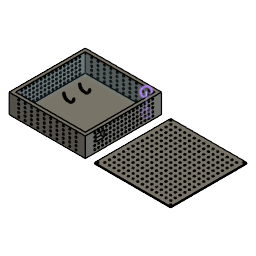
Air Quailty (Autodesk Fusion 360 design; units mm, degrees)
part number: 2026-01-30-16-34-56-412
Autodesk Fusion 360 part; units mm, degrees
sketch "Sketch1" plane through (0, 0, 0) normal (0, 1, 0) x (1, 0, 0)
  line L0 (52.5, -52.5) -> (-52.5, -52.5)
  line L1 (-52.5, -52.5) -> (-52.5, 52.5)
  line L2 (-52.5, 52.5) -> (52.5, 52.5)
  line L3 (52.5, 52.5) -> (52.5, -52.5)
  line L4 (52.5, -52.5) -> (-52.5, 52.5) construction
  line L5 (-52.5, -52.5) -> (52.5, 52.5) construction
  dimension "d1" = 105
  dimension "d2" = 105
  constraint horizontal L0
  constraint perpendicular L0 L1
  constraint parallel L0 L2
  constraint parallel L1 L3
  constraint coincident L4 origin
  constraint coincident L5 origin
  measures "d1" distance of L1.end L2.end
  measures "d2" distance of L0.end L1.end
extrude "Extrude1" add sketch "Sketch1" along normal blind 2 makes body 1
sketch "Sketch2" plane through (0, 2, 0) normal (0, 1, 0) x (-1, 0, 0)
  line L0 (-52.5, -52.5) -> (52.5, -52.5)
  line L1 (52.5, -52.5) -> (52.5, 52.5)
  line L2 (52.5, 52.5) -> (-52.5, 52.5)
  line L3 (-52.5, 52.5) -> (-52.5, -52.5)
  line L4 (-51.5, 51.5) -> (51.5, -51.5) construction
  line L5 (51.5, 51.5) -> (-51.5, -51.5) construction
  line L6 (-52.5, 52.5) -> (52.5, 52.5)
  line L7 (52.5, 52.5) -> (52.5, -52.5)
  line L8 (52.5, -52.5) -> (-52.5, -52.5)
  line L9 (-52.5, -52.5) -> (-52.5, 52.5)
  line L10 (-52.5, 52.5) -> (52.5, -52.5) construction
  line L11 (52.5, 52.5) -> (-52.5, -52.5) construction
  line L12 (50, 50) -> (-50, 50)
  line L13 (-50, 50) -> (-50, -50)
  line L14 (-50, -50) -> (50, -50)
  line L15 (50, -50) -> (50, 50)
  line L16 (50, 50) -> (-50, -50) construction
  line L17 (-50, 50) -> (50, -50) construction
  dimension "d5" = 103
  dimension "d6" = 103
  dimension "d7" = 105
  dimension "d8" = 105
  dimension "d9" = 100
  dimension "d10" = 100
  constraint coincident L4 origin
  constraint coincident L5 origin
  constraint horizontal L6
  constraint perpendicular L6 L7
  constraint parallel L6 L8
  constraint parallel L7 L9
  constraint coincident L10 origin
  constraint coincident L11 origin
  constraint horizontal L12
  constraint perpendicular L12 L13
  constraint parallel L12 L14
  constraint parallel L13 L15
  constraint coincident L16 origin
  constraint coincident L17 origin
  measures "d5" distance of L4.end L5.end
  measures "d6" distance of L5.start L4.end
  measures "d7" distance of L0.end L0.start
  measures "d8" distance of L1.end L0.end
  measures "d9" distance of L13.end L14.end
  measures "d10" distance of L12.end L13.end
extrude "Extrude2" add sketch "Sketch2" along normal blind 30 bodies 1
sketch "Sketch3" plane through (0, 0, -52.5) normal (0, 0, -1) x (-1, 0, 0)
  line L0 (-52.5, 0) -> (52.5, 0)
  line L1 (52.5, 0) -> (52.5, 32)
  line L2 (52.5, 32) -> (-52.5, 32)
  line L3 (-52.5, 32) -> (-52.5, 0)
  line L4 (-50, 2, -2.5) -> (-50, 32, -2.5)
sketch "Sketch4" plane through (0, 0, -50) normal (0, 0, 1) x (1, 0, 0)
  line L0 (-50, 2) -> (50, 2)
  line L1 (50, 2) -> (50, 32)
  line L2 (50, 32) -> (-50, 32)
  line L3 (-50, 32) -> (-50, 2)
  circle A0 centre (47.3769, 4.8478) radius 1.5
  circle A1 centre (36.9324, 4.8478) radius 1.5
  circle A2 centre (26.488, 4.8478) radius 1.5
  circle A3 centre (16.0435, 4.8478) radius 1.5
  circle A4 centre (5.5991, 4.8478) radius 1.5
  circle A5 centre (-4.8453, 4.8478) radius 1.5
  circle A6 centre (-15.2898, 4.8478) radius 1.5
  circle A7 centre (-25.7342, 4.8478) radius 1.5
  circle A8 centre (-36.1787, 4.8478) radius 1.5
  circle A9 centre (-46.6231, 4.8478) radius 1.5
  circle A10 centre (47.3769, 10.8478) radius 1.5
  circle A11 centre (36.9324, 10.8478) radius 1.5
  circle A12 centre (26.488, 10.8478) radius 1.5
  circle A13 centre (16.0435, 10.8478) radius 1.5
  circle A14 centre (5.5991, 10.8478) radius 1.5
  circle A15 centre (-4.8453, 10.8478) radius 1.5
  circle A16 centre (-15.2898, 10.8478) radius 1.5
  circle A17 centre (-25.7342, 10.8478) radius 1.5
  circle A18 centre (-36.1787, 10.8478) radius 1.5
  circle A19 centre (-46.6231, 10.8478) radius 1.5
  circle A20 centre (47.3769, 16.8478) radius 1.5
  circle A21 centre (36.9324, 16.8478) radius 1.5
  circle A22 centre (26.488, 16.8478) radius 1.5
  circle A23 centre (16.0435, 16.8478) radius 1.5
  circle A24 centre (5.5991, 16.8478) radius 1.5
  circle A25 centre (-4.8453, 16.8478) radius 1.5
  circle A26 centre (-15.2898, 16.8478) radius 1.5
  circle A27 centre (-25.7342, 16.8478) radius 1.5
  circle A28 centre (-36.1787, 16.8478) radius 1.5
  circle A29 centre (-46.6231, 16.8478) radius 1.5
  circle A30 centre (47.3769, 22.8478) radius 1.5
  circle A31 centre (36.9324, 22.8478) radius 1.5
  circle A32 centre (26.488, 22.8478) radius 1.5
  circle A33 centre (16.0435, 22.8478) radius 1.5
  circle A34 centre (5.5991, 22.8478) radius 1.5
  circle A35 centre (-4.8453, 22.8478) radius 1.5
  circle A36 centre (-15.2898, 22.8478) radius 1.5
  circle A37 centre (-25.7342, 22.8478) radius 1.5
  circle A38 centre (-36.1787, 22.8478) radius 1.5
  circle A39 centre (-46.6231, 22.8478) radius 1.5
  circle A40 centre (47.3769, 28.8478) radius 1.5
  circle A41 centre (36.9324, 28.8478) radius 1.5
  circle A42 centre (26.488, 28.8478) radius 1.5
  circle A43 centre (16.0435, 28.8478) radius 1.5
  circle A44 centre (5.5991, 28.8478) radius 1.5
  circle A45 centre (-4.8453, 28.8478) radius 1.5
  circle A46 centre (-15.2898, 28.8478) radius 1.5
  circle A47 centre (-25.7342, 28.8478) radius 1.5
  circle A48 centre (-36.1787, 28.8478) radius 1.5
  circle A49 centre (-46.6231, 28.8478) radius 1.5
  dimension "d14" = 3
  dimension "d17" = 94
  dimension "d18" = -24
  measures "d14" diameter of A0
extrude "Extrude3" cut sketch "Sketch4" along normal blind 124 and the other way blind 26 contours A0 | A1 | A2 | A3 | A4 | A5 | A6 | A7 | A8 | A9 | A10 | A11 | A12 | A13 | A14 | A15 | A16 | A17 | A18 | A19 | A20 | A21 | A22 | A23 | A24 | A25 | A26 | A27 | A28 | A29 | A30 | A31 | A32 | A33 | A34 | A35 | A36 | A37 | A38 | A39 | A40 | A41 | A42 | A43 | A44 | A45 | A46 | A47 | A48 | A49 bodies 1
sketch "Sketch5" plane through (-52.5, 0, 0) normal (-1, 0, 0) x (0, 0, 1)
  line L0 (-52.5, 0) -> (52.5, 0)
  line L1 (52.5, 0) -> (52.5, 32)
  line L2 (52.5, 32) -> (-52.5, 32)
  line L3 (-52.5, 32) -> (-52.5, 0)
sketch "Sketch6" plane through (-50, 0, 0) normal (1, 0, 0) x (0, 0, -1)
  line L0 (-50, 2) -> (50, 2)
  line L1 (50, 2) -> (50, 32)
  line L2 (50, 32) -> (-50, 32)
  line L3 (-50, 32) -> (-50, 2)
  circle A0 centre (-47, 5) radius 1.5
  circle A1 centre (-40.6667, 5) radius 1.5
  line L4 (56.3333, 32) -> (-43.6667, 32)
  line L5 (-43.6667, 32) -> (-43.6667, 2)
  circle A2 centre (-34.3333, 5) radius 1.5
  line L6 (62.6667, 32) -> (-37.3333, 32)
  line L7 (-37.3333, 32) -> (-37.3333, 2)
  circle A3 centre (-28, 5) radius 1.5
  line L8 (69, 32) -> (-31, 32)
  line L9 (-31, 32) -> (-31, 2)
  circle A4 centre (-21.6667, 5) radius 1.5
  line L10 (75.3333, 32) -> (-24.6667, 32)
  line L11 (-24.6667, 32) -> (-24.6667, 2)
  circle A5 centre (-15.3333, 5) radius 1.5
  line L12 (81.6667, 32) -> (-18.3333, 32)
  line L13 (-18.3333, 32) -> (-18.3333, 2)
  circle A6 centre (-9, 5) radius 1.5
  line L14 (88, 32) -> (-12, 32)
  line L15 (-12, 32) -> (-12, 2)
  circle A7 centre (-2.6667, 5) radius 1.5
  line L16 (94.3333, 32) -> (-5.6667, 32)
  line L17 (-5.6667, 32) -> (-5.6667, 2)
  circle A8 centre (3.6667, 5) radius 1.5
  line L18 (100.6667, 32) -> (0.6667, 32)
  line L19 (0.6667, 32) -> (0.6667, 2)
  circle A9 centre (10, 5) radius 1.5
  line L20 (107, 32) -> (7, 32)
  line L21 (7, 32) -> (7, 2)
  circle A10 centre (16.3333, 5) radius 1.5
  line L22 (113.3333, 32) -> (13.3333, 32)
  line L23 (13.3333, 32) -> (13.3333, 2)
  circle A11 centre (22.6667, 5) radius 1.5
  line L24 (119.6667, 32) -> (19.6667, 32)
  line L25 (19.6667, 32) -> (19.6667, 2)
  circle A12 centre (29, 5) radius 1.5
  line L26 (126, 32) -> (26, 32)
  line L27 (26, 32) -> (26, 2)
  circle A13 centre (35.3333, 5) radius 1.5
  line L28 (132.3333, 32) -> (32.3333, 32)
  line L29 (32.3333, 32) -> (32.3333, 2)
  circle A14 centre (41.6667, 5) radius 1.5
  line L30 (138.6667, 32) -> (38.6667, 32)
  line L31 (38.6667, 32) -> (38.6667, 2)
  circle A15 centre (48, 5) radius 1.5
  line L32 (145, 32) -> (45, 32)
  line L33 (45, 32) -> (45, 2)
  circle A16 centre (-47, 11) radius 1.5
  line L34 (50, 38) -> (-50, 38)
  line L35 (-50, 38) -> (-50, 8)
  circle A17 centre (-40.6667, 11) radius 1.5
  line L36 (56.3333, 38) -> (-43.6667, 38)
  line L37 (-43.6667, 38) -> (-43.6667, 8)
  circle A18 centre (-34.3333, 11) radius 1.5
  line L38 (62.6667, 38) -> (-37.3333, 38)
  line L39 (-37.3333, 38) -> (-37.3333, 8)
  circle A19 centre (-28, 11) radius 1.5
  line L40 (69, 38) -> (-31, 38)
  line L41 (-31, 38) -> (-31, 8)
  circle A20 centre (-21.6667, 11) radius 1.5
  line L42 (75.3333, 38) -> (-24.6667, 38)
  line L43 (-24.6667, 38) -> (-24.6667, 8)
  circle A21 centre (-15.3333, 11) radius 1.5
  line L44 (81.6667, 38) -> (-18.3333, 38)
  line L45 (-18.3333, 38) -> (-18.3333, 8)
  circle A22 centre (-9, 11) radius 1.5
  line L46 (88, 38) -> (-12, 38)
  line L47 (-12, 38) -> (-12, 8)
  circle A23 centre (-2.6667, 11) radius 1.5
  line L48 (94.3333, 38) -> (-5.6667, 38)
  line L49 (-5.6667, 38) -> (-5.6667, 8)
  circle A24 centre (3.6667, 11) radius 1.5
  line L50 (100.6667, 38) -> (0.6667, 38)
  line L51 (0.6667, 38) -> (0.6667, 8)
  circle A25 centre (10, 11) radius 1.5
  line L52 (107, 38) -> (7, 38)
  line L53 (7, 38) -> (7, 8)
  circle A26 centre (16.3333, 11) radius 1.5
  line L54 (113.3333, 38) -> (13.3333, 38)
  line L55 (13.3333, 38) -> (13.3333, 8)
  circle A27 centre (22.6667, 11) radius 1.5
  line L56 (119.6667, 38) -> (19.6667, 38)
  line L57 (19.6667, 38) -> (19.6667, 8)
  circle A28 centre (29, 11) radius 1.5
  line L58 (126, 38) -> (26, 38)
  line L59 (26, 38) -> (26, 8)
  circle A29 centre (35.3333, 11) radius 1.5
  line L60 (132.3333, 38) -> (32.3333, 38)
  line L61 (32.3333, 38) -> (32.3333, 8)
  circle A30 centre (41.6667, 11) radius 1.5
  line L62 (138.6667, 38) -> (38.6667, 38)
  line L63 (38.6667, 38) -> (38.6667, 8)
  circle A31 centre (48, 11) radius 1.5
  line L64 (145, 38) -> (45, 38)
  line L65 (45, 38) -> (45, 8)
  circle A32 centre (-47, 17) radius 1.5
  line L66 (50, 44) -> (-50, 44)
  line L67 (-50, 44) -> (-50, 14)
  circle A33 centre (-40.6667, 17) radius 1.5
  line L68 (56.3333, 44) -> (-43.6667, 44)
  line L69 (-43.6667, 44) -> (-43.6667, 14)
  circle A34 centre (-34.3333, 17) radius 1.5
  line L70 (62.6667, 44) -> (-37.3333, 44)
  line L71 (-37.3333, 44) -> (-37.3333, 14)
  circle A35 centre (-28, 17) radius 1.5
  line L72 (69, 44) -> (-31, 44)
  line L73 (-31, 44) -> (-31, 14)
  circle A36 centre (-21.6667, 17) radius 1.5
  line L74 (75.3333, 44) -> (-24.6667, 44)
  line L75 (-24.6667, 44) -> (-24.6667, 14)
  circle A37 centre (-15.3333, 17) radius 1.5
  line L76 (81.6667, 44) -> (-18.3333, 44)
  line L77 (-18.3333, 44) -> (-18.3333, 14)
  circle A38 centre (-9, 17) radius 1.5
  line L78 (88, 44) -> (-12, 44)
  line L79 (-12, 44) -> (-12, 14)
  circle A39 centre (-2.6667, 17) radius 1.5
  line L80 (94.3333, 44) -> (-5.6667, 44)
  line L81 (-5.6667, 44) -> (-5.6667, 14)
  circle A40 centre (3.6667, 17) radius 1.5
  line L82 (100.6667, 44) -> (0.6667, 44)
  line L83 (0.6667, 44) -> (0.6667, 14)
  circle A41 centre (10, 17) radius 1.5
  line L84 (107, 44) -> (7, 44)
  line L85 (7, 44) -> (7, 14)
  circle A42 centre (16.3333, 17) radius 1.5
  line L86 (113.3333, 44) -> (13.3333, 44)
  line L87 (13.3333, 44) -> (13.3333, 14)
  circle A43 centre (22.6667, 17) radius 1.5
  line L88 (119.6667, 44) -> (19.6667, 44)
  line L89 (19.6667, 44) -> (19.6667, 14)
  circle A44 centre (29, 17) radius 1.5
  line L90 (126, 44) -> (26, 44)
  line L91 (26, 44) -> (26, 14)
  circle A45 centre (35.3333, 17) radius 1.5
  line L92 (132.3333, 44) -> (32.3333, 44)
  line L93 (32.3333, 44) -> (32.3333, 14)
  circle A46 centre (41.6667, 17) radius 1.5
  line L94 (138.6667, 44) -> (38.6667, 44)
  line L95 (38.6667, 44) -> (38.6667, 14)
  circle A47 centre (48, 17) radius 1.5
  line L96 (145, 44) -> (45, 44)
  line L97 (45, 44) -> (45, 14)
  circle A48 centre (-47, 23) radius 1.5
  line L98 (50, 50) -> (-50, 50)
  line L99 (-50, 50) -> (-50, 20)
  circle A49 centre (-40.6667, 23) radius 1.5
  line L100 (56.3333, 50) -> (-43.6667, 50)
  line L101 (-43.6667, 50) -> (-43.6667, 20)
  circle A50 centre (-34.3333, 23) radius 1.5
  line L102 (62.6667, 50) -> (-37.3333, 50)
  line L103 (-37.3333, 50) -> (-37.3333, 20)
  circle A51 centre (-28, 23) radius 1.5
  line L104 (69, 50) -> (-31, 50)
  line L105 (-31, 50) -> (-31, 20)
  circle A52 centre (-21.6667, 23) radius 1.5
  line L106 (75.3333, 50) -> (-24.6667, 50)
  line L107 (-24.6667, 50) -> (-24.6667, 20)
  circle A53 centre (-15.3333, 23) radius 1.5
  line L108 (81.6667, 50) -> (-18.3333, 50)
  line L109 (-18.3333, 50) -> (-18.3333, 20)
  circle A54 centre (-9, 23) radius 1.5
  line L110 (88, 50) -> (-12, 50)
  line L111 (-12, 50) -> (-12, 20)
  circle A55 centre (-2.6667, 23) radius 1.5
  line L112 (94.3333, 50) -> (-5.6667, 50)
  line L113 (-5.6667, 50) -> (-5.6667, 20)
  circle A56 centre (3.6667, 23) radius 1.5
  line L114 (100.6667, 50) -> (0.6667, 50)
  line L115 (0.6667, 50) -> (0.6667, 20)
  circle A57 centre (10, 23) radius 1.5
  line L116 (107, 50) -> (7, 50)
  line L117 (7, 50) -> (7, 20)
  circle A58 centre (16.3333, 23) radius 1.5
  line L118 (113.3333, 50) -> (13.3333, 50)
  line L119 (13.3333, 50) -> (13.3333, 20)
  circle A59 centre (22.6667, 23) radius 1.5
  line L120 (119.6667, 50) -> (19.6667, 50)
  line L121 (19.6667, 50) -> (19.6667, 20)
  circle A60 centre (29, 23) radius 1.5
  line L122 (126, 50) -> (26, 50)
  line L123 (26, 50) -> (26, 20)
  circle A61 centre (35.3333, 23) radius 1.5
  line L124 (132.3333, 50) -> (32.3333, 50)
  line L125 (32.3333, 50) -> (32.3333, 20)
  circle A62 centre (41.6667, 23) radius 1.5
  line L126 (138.6667, 50) -> (38.6667, 50)
  line L127 (38.6667, 50) -> (38.6667, 20)
  circle A63 centre (48, 23) radius 1.5
  line L128 (145, 50) -> (45, 50)
  line L129 (45, 50) -> (45, 20)
  circle A64 centre (-47, 29) radius 1.5
  line L130 (50, 56) -> (-50, 56)
  line L131 (-50, 56) -> (-50, 26)
  circle A65 centre (-40.6667, 29) radius 1.5
  line L132 (56.3333, 56) -> (-43.6667, 56)
  line L133 (-43.6667, 56) -> (-43.6667, 26)
  circle A66 centre (-34.3333, 29) radius 1.5
  line L134 (62.6667, 56) -> (-37.3333, 56)
  line L135 (-37.3333, 56) -> (-37.3333, 26)
  circle A67 centre (-28, 29) radius 1.5
  line L136 (69, 56) -> (-31, 56)
  line L137 (-31, 56) -> (-31, 26)
  circle A68 centre (-21.6667, 29) radius 1.5
  line L138 (75.3333, 56) -> (-24.6667, 56)
  line L139 (-24.6667, 56) -> (-24.6667, 26)
  circle A69 centre (-15.3333, 29) radius 1.5
  line L140 (81.6667, 56) -> (-18.3333, 56)
  line L141 (-18.3333, 56) -> (-18.3333, 26)
  circle A70 centre (-9, 29) radius 1.5
  line L142 (88, 56) -> (-12, 56)
  line L143 (-12, 56) -> (-12, 26)
  circle A71 centre (-2.6667, 29) radius 1.5
  line L144 (94.3333, 56) -> (-5.6667, 56)
  line L145 (-5.6667, 56) -> (-5.6667, 26)
  circle A72 centre (3.6667, 29) radius 1.5
  line L146 (100.6667, 56) -> (0.6667, 56)
  line L147 (0.6667, 56) -> (0.6667, 26)
  circle A73 centre (10, 29) radius 1.5
  line L148 (107, 56) -> (7, 56)
  line L149 (7, 56) -> (7, 26)
  circle A74 centre (16.3333, 29) radius 1.5
  line L150 (113.3333, 56) -> (13.3333, 56)
  line L151 (13.3333, 56) -> (13.3333, 26)
  circle A75 centre (22.6667, 29) radius 1.5
  line L152 (119.6667, 56) -> (19.6667, 56)
  line L153 (19.6667, 56) -> (19.6667, 26)
  circle A76 centre (29, 29) radius 1.5
  line L154 (126, 56) -> (26, 56)
  line L155 (26, 56) -> (26, 26)
  circle A77 centre (35.3333, 29) radius 1.5
  line L156 (132.3333, 56) -> (32.3333, 56)
  line L157 (32.3333, 56) -> (32.3333, 26)
  circle A78 centre (41.6667, 29) radius 1.5
  line L158 (138.6667, 56) -> (38.6667, 56)
  line L159 (38.6667, 56) -> (38.6667, 26)
  circle A79 centre (48, 29) radius 1.5
  line L160 (145, 56) -> (45, 56)
  line L161 (45, 56) -> (45, 26)
  dimension "d23" = 3
  dimension "d26" = 95
  dimension "d27" = 24
  measures "d23" diameter of A0
extrude "Extrude4" cut sketch "Sketch6" along normal blind 119 and the other way blind 26 contours A0 | A1 | A2 | A3 | A16 | A17 | A18 | A19 | A32 | A33 | A34 | A35 | A48 | A49 | A50 | A51 | A64 | A65 | A66 | A67 bodies 1
extrude "Extrude5" cut sketch "Sketch6" along normal mid plane 250 contours A4 | A5 | A6 | A7 | A8 | A9 | A20 | A21 | A22 | A23 | A24 | A25 | A36 | A37 | A38 | A39 | A40 | A41 | A52 | A53 | A54 | A55 | A56 | A57 | A68 | A69 | A70 | A71 | A72 | A73 bodies 1
extrude "Extrude6" cut sketch "Sketch6" along normal blind 125 and the other way blind 9 contours A10 | A11 | A12 | A13 | A14 | A15 | A26 | A27 | A28 | A29 | A30 | A31 | A42 | A43 | A44 | A45 | A46 | A47 | A58 | A59 | A60 | A61 | A62 | A63 | A74 | A75 | A76 | A77 | A78 | A79 bodies 1
move_face "OffsetFaces1" offset -2 4 faces at (-50, 20.6599, -20.189) (-8.7773, 20.6309, -50) (50, 19.3401, 6.5224) (-11.3578, 19.0647, 50) on bodies 1
sketch "Sketch8" plane through (0, 32, 0) normal (0, 1, 0) x (-1, 0, 0)
  line L0 (-52.5, -52.5) -> (52.5, -52.5)
  line L1 (52.5, -52.5) -> (52.5, 52.5)
  line L2 (52.5, 52.5) -> (-52.5, 52.5)
  line L3 (-52.5, 52.5) -> (-52.5, -52.5)
  circle A0 centre (-50.25, 50.25) radius 1.5
  circle A1 centre (50.25, 50.25) radius 1.5
  circle A2 centre (-50.25, -50.25) radius 1.5
  circle A3 centre (50.25, -50.25) radius 1.5
  circle A4 centre (-45, 45) radius 1.5
  circle A5 centre (-38.6429, 45) radius 1.5
  circle A6 centre (-32.2857, 45) radius 1.5
  circle A7 centre (-25.9286, 45) radius 1.5
  circle A8 centre (-19.5714, 45) radius 1.5
  circle A9 centre (-13.2143, 45) radius 1.5
  circle A10 centre (-6.8571, 45) radius 1.5
  circle A11 centre (-0.5, 45) radius 1.5
  circle A12 centre (5.8571, 45) radius 1.5
  circle A13 centre (12.2143, 45) radius 1.5
  circle A14 centre (18.5714, 45) radius 1.5
  circle A15 centre (24.9286, 45) radius 1.5
  circle A16 centre (31.2857, 45) radius 1.5
  circle A17 centre (37.6429, 45) radius 1.5
  circle A18 centre (44, 45) radius 1.5
  circle A19 centre (-45, 38.6429) radius 1.5
  circle A20 centre (-38.6429, 38.6429) radius 1.5
  circle A21 centre (-32.2857, 38.6429) radius 1.5
  circle A22 centre (-25.9286, 38.6429) radius 1.5
  circle A23 centre (-19.5714, 38.6429) radius 1.5
  circle A24 centre (-13.2143, 38.6429) radius 1.5
  circle A25 centre (-6.8571, 38.6429) radius 1.5
  circle A26 centre (-0.5, 38.6429) radius 1.5
  circle A27 centre (5.8571, 38.6429) radius 1.5
  circle A28 centre (12.2143, 38.6429) radius 1.5
  circle A29 centre (18.5714, 38.6429) radius 1.5
  circle A30 centre (24.9286, 38.6429) radius 1.5
  circle A31 centre (31.2857, 38.6429) radius 1.5
  circle A32 centre (37.6429, 38.6429) radius 1.5
  circle A33 centre (44, 38.6429) radius 1.5
  circle A34 centre (-45, 32.2857) radius 1.5
  circle A35 centre (-38.6429, 32.2857) radius 1.5
  circle A36 centre (-32.2857, 32.2857) radius 1.5
  circle A37 centre (-25.9286, 32.2857) radius 1.5
  circle A38 centre (-19.5714, 32.2857) radius 1.5
  circle A39 centre (-13.2143, 32.2857) radius 1.5
  circle A40 centre (-6.8571, 32.2857) radius 1.5
  circle A41 centre (-0.5, 32.2857) radius 1.5
  circle A42 centre (5.8571, 32.2857) radius 1.5
  circle A43 centre (12.2143, 32.2857) radius 1.5
  circle A44 centre (18.5714, 32.2857) radius 1.5
  circle A45 centre (24.9286, 32.2857) radius 1.5
  circle A46 centre (31.2857, 32.2857) radius 1.5
  circle A47 centre (37.6429, 32.2857) radius 1.5
  circle A48 centre (44, 32.2857) radius 1.5
  circle A49 centre (-45, 25.9286) radius 1.5
  circle A50 centre (-38.6429, 25.9286) radius 1.5
  circle A51 centre (-32.2857, 25.9286) radius 1.5
  circle A52 centre (-25.9286, 25.9286) radius 1.5
  circle A53 centre (-19.5714, 25.9286) radius 1.5
  circle A54 centre (-13.2143, 25.9286) radius 1.5
  circle A55 centre (-6.8571, 25.9286) radius 1.5
  circle A56 centre (-0.5, 25.9286) radius 1.5
  circle A57 centre (5.8571, 25.9286) radius 1.5
  circle A58 centre (12.2143, 25.9286) radius 1.5
  circle A59 centre (18.5714, 25.9286) radius 1.5
  circle A60 centre (24.9286, 25.9286) radius 1.5
  circle A61 centre (31.2857, 25.9286) radius 1.5
  circle A62 centre (37.6429, 25.9286) radius 1.5
  circle A63 centre (44, 25.9286) radius 1.5
  circle A64 centre (-45, 19.5714) radius 1.5
  circle A65 centre (-38.6429, 19.5714) radius 1.5
  circle A66 centre (-32.2857, 19.5714) radius 1.5
  circle A67 centre (-25.9286, 19.5714) radius 1.5
  circle A68 centre (-19.5714, 19.5714) radius 1.5
  circle A69 centre (-13.2143, 19.5714) radius 1.5
  circle A70 centre (-6.8571, 19.5714) radius 1.5
  circle A71 centre (-0.5, 19.5714) radius 1.5
  circle A72 centre (5.8571, 19.5714) radius 1.5
  circle A73 centre (12.2143, 19.5714) radius 1.5
  circle A74 centre (18.5714, 19.5714) radius 1.5
  circle A75 centre (24.9286, 19.5714) radius 1.5
  circle A76 centre (31.2857, 19.5714) radius 1.5
  circle A77 centre (37.6429, 19.5714) radius 1.5
  circle A78 centre (44, 19.5714) radius 1.5
  circle A79 centre (-45, 13.2143) radius 1.5
  circle A80 centre (-38.6429, 13.2143) radius 1.5
  circle A81 centre (-32.2857, 13.2143) radius 1.5
  circle A82 centre (-25.9286, 13.2143) radius 1.5
  circle A83 centre (-19.5714, 13.2143) radius 1.5
  circle A84 centre (-13.2143, 13.2143) radius 1.5
  circle A85 centre (-6.8571, 13.2143) radius 1.5
  circle A86 centre (-0.5, 13.2143) radius 1.5
  circle A87 centre (5.8571, 13.2143) radius 1.5
  circle A88 centre (12.2143, 13.2143) radius 1.5
  circle A89 centre (18.5714, 13.2143) radius 1.5
  circle A90 centre (24.9286, 13.2143) radius 1.5
  circle A91 centre (31.2857, 13.2143) radius 1.5
  circle A92 centre (37.6429, 13.2143) radius 1.5
  circle A93 centre (44, 13.2143) radius 1.5
  circle A94 centre (-45, 6.8571) radius 1.5
  circle A95 centre (-38.6429, 6.8571) radius 1.5
  circle A96 centre (-32.2857, 6.8571) radius 1.5
  circle A97 centre (-25.9286, 6.8571) radius 1.5
  circle A98 centre (-19.5714, 6.8571) radius 1.5
  circle A99 centre (-13.2143, 6.8571) radius 1.5
  circle A100 centre (-6.8571, 6.8571) radius 1.5
  circle A101 centre (-0.5, 6.8571) radius 1.5
  circle A102 centre (5.8571, 6.8571) radius 1.5
  circle A103 centre (12.2143, 6.8571) radius 1.5
  circle A104 centre (18.5714, 6.8571) radius 1.5
  circle A105 centre (24.9286, 6.8571) radius 1.5
  circle A106 centre (31.2857, 6.8571) radius 1.5
  circle A107 centre (37.6429, 6.8571) radius 1.5
  circle A108 centre (44, 6.8571) radius 1.5
  circle A109 centre (-45, 0.5) radius 1.5
  circle A110 centre (-38.6429, 0.5) radius 1.5
  circle A111 centre (-32.2857, 0.5) radius 1.5
  circle A112 centre (-25.9286, 0.5) radius 1.5
  circle A113 centre (-19.5714, 0.5) radius 1.5
  circle A114 centre (-13.2143, 0.5) radius 1.5
  circle A115 centre (-6.8571, 0.5) radius 1.5
  circle A116 centre (-0.5, 0.5) radius 1.5
  circle A117 centre (5.8571, 0.5) radius 1.5
  circle A118 centre (12.2143, 0.5) radius 1.5
  circle A119 centre (18.5714, 0.5) radius 1.5
  circle A120 centre (24.9286, 0.5) radius 1.5
  circle A121 centre (31.2857, 0.5) radius 1.5
  circle A122 centre (37.6429, 0.5) radius 1.5
  circle A123 centre (44, 0.5) radius 1.5
  circle A124 centre (-45, -5.8571) radius 1.5
  circle A125 centre (-38.6429, -5.8571) radius 1.5
  circle A126 centre (-32.2857, -5.8571) radius 1.5
  circle A127 centre (-25.9286, -5.8571) radius 1.5
  circle A128 centre (-19.5714, -5.8571) radius 1.5
  circle A129 centre (-13.2143, -5.8571) radius 1.5
  circle A130 centre (-6.8571, -5.8571) radius 1.5
  circle A131 centre (-0.5, -5.8571) radius 1.5
  circle A132 centre (5.8571, -5.8571) radius 1.5
  circle A133 centre (12.2143, -5.8571) radius 1.5
  circle A134 centre (18.5714, -5.8571) radius 1.5
  circle A135 centre (24.9286, -5.8571) radius 1.5
  circle A136 centre (31.2857, -5.8571) radius 1.5
  circle A137 centre (37.6429, -5.8571) radius 1.5
  circle A138 centre (44, -5.8571) radius 1.5
  circle A139 centre (-45, -12.2143) radius 1.5
  circle A140 centre (-38.6429, -12.2143) radius 1.5
  circle A141 centre (-32.2857, -12.2143) radius 1.5
  circle A142 centre (-25.9286, -12.2143) radius 1.5
  circle A143 centre (-19.5714, -12.2143) radius 1.5
  circle A144 centre (-13.2143, -12.2143) radius 1.5
  circle A145 centre (-6.8571, -12.2143) radius 1.5
  circle A146 centre (-0.5, -12.2143) radius 1.5
  circle A147 centre (5.8571, -12.2143) radius 1.5
  circle A148 centre (12.2143, -12.2143) radius 1.5
  circle A149 centre (18.5714, -12.2143) radius 1.5
  circle A150 centre (24.9286, -12.2143) radius 1.5
  circle A151 centre (31.2857, -12.2143) radius 1.5
  circle A152 centre (37.6429, -12.2143) radius 1.5
  circle A153 centre (44, -12.2143) radius 1.5
  circle A154 centre (-45, -18.5714) radius 1.5
  circle A155 centre (-38.6429, -18.5714) radius 1.5
  circle A156 centre (-32.2857, -18.5714) radius 1.5
  circle A157 centre (-25.9286, -18.5714) radius 1.5
  circle A158 centre (-19.5714, -18.5714) radius 1.5
  circle A159 centre (-13.2143, -18.5714) radius 1.5
  circle A160 centre (-6.8571, -18.5714) radius 1.5
  circle A161 centre (-0.5, -18.5714) radius 1.5
  circle A162 centre (5.8571, -18.5714) radius 1.5
  circle A163 centre (12.2143, -18.5714) radius 1.5
  circle A164 centre (18.5714, -18.5714) radius 1.5
  circle A165 centre (24.9286, -18.5714) radius 1.5
  circle A166 centre (31.2857, -18.5714) radius 1.5
  circle A167 centre (37.6429, -18.5714) radius 1.5
  circle A168 centre (44, -18.5714) radius 1.5
  circle A169 centre (-45, -24.9286) radius 1.5
  circle A170 centre (-38.6429, -24.9286) radius 1.5
  circle A171 centre (-32.2857, -24.9286) radius 1.5
  circle A172 centre (-25.9286, -24.9286) radius 1.5
  circle A173 centre (-19.5714, -24.9286) radius 1.5
  circle A174 centre (-13.2143, -24.9286) radius 1.5
  circle A175 centre (-6.8571, -24.9286) radius 1.5
  circle A176 centre (-0.5, -24.9286) radius 1.5
  circle A177 centre (5.8571, -24.9286) radius 1.5
  circle A178 centre (12.2143, -24.9286) radius 1.5
  circle A179 centre (18.5714, -24.9286) radius 1.5
  circle A180 centre (24.9286, -24.9286) radius 1.5
  circle A181 centre (31.2857, -24.9286) radius 1.5
  circle A182 centre (37.6429, -24.9286) radius 1.5
  circle A183 centre (44, -24.9286) radius 1.5
  circle A184 centre (-45, -31.2857) radius 1.5
  circle A185 centre (-38.6429, -31.2857) radius 1.5
  circle A186 centre (-32.2857, -31.2857) radius 1.5
  circle A187 centre (-25.9286, -31.2857) radius 1.5
  circle A188 centre (-19.5714, -31.2857) radius 1.5
  circle A189 centre (-13.2143, -31.2857) radius 1.5
  circle A190 centre (-6.8571, -31.2857) radius 1.5
  circle A191 centre (-0.5, -31.2857) radius 1.5
  circle A192 centre (5.8571, -31.2857) radius 1.5
  circle A193 centre (12.2143, -31.2857) radius 1.5
  circle A194 centre (18.5714, -31.2857) radius 1.5
  circle A195 centre (24.9286, -31.2857) radius 1.5
  circle A196 centre (31.2857, -31.2857) radius 1.5
  circle A197 centre (37.6429, -31.2857) radius 1.5
  circle A198 centre (44, -31.2857) radius 1.5
  circle A199 centre (-45, -37.6429) radius 1.5
  circle A200 centre (-38.6429, -37.6429) radius 1.5
  circle A201 centre (-32.2857, -37.6429) radius 1.5
  circle A202 centre (-25.9286, -37.6429) radius 1.5
  circle A203 centre (-19.5714, -37.6429) radius 1.5
  circle A204 centre (-13.2143, -37.6429) radius 1.5
  circle A205 centre (-6.8571, -37.6429) radius 1.5
  circle A206 centre (-0.5, -37.6429) radius 1.5
  circle A207 centre (5.8571, -37.6429) radius 1.5
  circle A208 centre (12.2143, -37.6429) radius 1.5
  circle A209 centre (18.5714, -37.6429) radius 1.5
  circle A210 centre (24.9286, -37.6429) radius 1.5
  circle A211 centre (31.2857, -37.6429) radius 1.5
  circle A212 centre (37.6429, -37.6429) radius 1.5
  circle A213 centre (44, -37.6429) radius 1.5
  circle A214 centre (-45, -44) radius 1.5
  circle A215 centre (-38.6429, -44) radius 1.5
  circle A216 centre (-32.2857, -44) radius 1.5
  circle A217 centre (-25.9286, -44) radius 1.5
  circle A218 centre (-19.5714, -44) radius 1.5
  circle A219 centre (-13.2143, -44) radius 1.5
  circle A220 centre (-6.8571, -44) radius 1.5
  circle A221 centre (-0.5, -44) radius 1.5
  circle A222 centre (5.8571, -44) radius 1.5
  circle A223 centre (12.2143, -44) radius 1.5
  circle A224 centre (18.5714, -44) radius 1.5
  circle A225 centre (24.9286, -44) radius 1.5
  circle A226 centre (31.2857, -44) radius 1.5
  circle A227 centre (37.6429, -44) radius 1.5
  circle A228 centre (44, -44) radius 1.5
  dimension "d42" = 3
  dimension "d47" = 3
  dimension "d50" = 89
  dimension "d51" = 89
  measures "d42" diameter of A0
  measures "d47" diameter of A4
sketch "Sketch9" plane through (52, 0, 0) normal (-1, 0, 0) x (0, 0, 1)
  circle A0 centre (-41.6667, 11) radius 1.5
  circle A1 centre (-35.3333, 29) radius 1.5
  circle A2 centre (-35.3333, 5) radius 1.5
  circle A3 centre (-29, 23) radius 1.5
  circle A4 centre (-22.6667, 17) radius 1.5
  circle A5 centre (-16.3333, 11) radius 1.5
  circle A6 centre (-16.3333, 29) radius 1.5
  circle A7 centre (-16.3333, 5) radius 1.5
  circle A8 centre (-22.6667, 23) radius 1.5
  circle A9 centre (-29, 17) radius 1.5
  circle A10 centre (-35.3333, 11) radius 1.5
  circle A11 centre (-41.6667, 29) radius 1.5
  circle A12 centre (-41.6667, 5) radius 1.5
  circle A13 centre (-41.6667, 17) radius 1.5
  circle A14 centre (-35.3333, 23) radius 1.5
  circle A15 centre (-29, 5) radius 1.5
  circle A16 centre (-29, 29) radius 1.5
  circle A17 centre (-22.6667, 11) radius 1.5
  circle A18 centre (-16.3333, 17) radius 1.5
  circle A19 centre (-16.3333, 23) radius 1.5
  circle A20 centre (-22.6667, 5) radius 1.5
  circle A21 centre (-22.6667, 29) radius 1.5
  circle A22 centre (-29, 11) radius 1.5
  circle A23 centre (-35.3333, 17) radius 1.5
  circle A24 centre (-41.6667, 23) radius 1.5
  circle A25 centre (-10, 17) radius 1.5
  circle A26 centre (-3.6667, 11) radius 1.5
  circle A27 centre (2.6667, 29) radius 1.5
  circle A28 centre (2.6667, 5) radius 1.5
  circle A29 centre (9, 23) radius 1.5
  circle A30 centre (15.3333, 17) radius 1.5
  circle A31 centre (21.6667, 11) radius 1.5
  circle A32 centre (21.6667, 29) radius 1.5
  circle A33 centre (21.6667, 5) radius 1.5
  circle A34 centre (15.3333, 23) radius 1.5
  circle A35 centre (9, 17) radius 1.5
  circle A36 centre (2.6667, 11) radius 1.5
  circle A37 centre (-3.6667, 29) radius 1.5
  circle A38 centre (-3.6667, 5) radius 1.5
  circle A39 centre (-10, 23) radius 1.5
  circle A40 centre (-10, 11) radius 1.5
  circle A41 centre (-3.6667, 17) radius 1.5
  circle A42 centre (2.6667, 23) radius 1.5
  circle A43 centre (9, 5) radius 1.5
  circle A44 centre (9, 29) radius 1.5
  circle A45 centre (15.3333, 11) radius 1.5
  circle A46 centre (21.6667, 17) radius 1.5
  circle A47 centre (21.6667, 23) radius 1.5
  circle A48 centre (15.3333, 5) radius 1.5
  circle A49 centre (15.3333, 29) radius 1.5
  circle A50 centre (9, 11) radius 1.5
  circle A51 centre (2.6667, 17) radius 1.5
  circle A52 centre (-3.6667, 23) radius 1.5
  circle A53 centre (-10, 5) radius 1.5
  circle A54 centre (-10, 29) radius 1.5
  circle A55 centre (28, 17) radius 1.5
  circle A56 centre (34.3333, 11) radius 1.5
  circle A57 centre (40.6667, 29) radius 1.5
  circle A58 centre (40.6667, 5) radius 1.5
  circle A59 centre (40.6667, 11) radius 1.5
  circle A60 centre (34.3333, 29) radius 1.5
  circle A61 centre (34.3333, 5) radius 1.5
  circle A62 centre (28, 23) radius 1.5
  circle A63 centre (28, 11) radius 1.5
  circle A64 centre (34.3333, 17) radius 1.5
  circle A65 centre (40.6667, 23) radius 1.5
  line L0 (52, 32) -> (-52, 32)
  line L1 (-52, 32) -> (-52, 2)
  line L2 (-52, 2) -> (52, 2)
  line L3 (52, 2) -> (52, 32)
  circle A66 centre (40.6667, 17) radius 1.5
  circle A67 centre (34.3333, 23) radius 1.5
  circle A68 centre (28, 5) radius 1.5
  circle A69 centre (28, 29) radius 1.5
  line L4 (45, 15) -> (31.5, 15)
  line L5 (31.5, 15) -> (31.5, 25.5)
  line L6 (31.5, 25.5) -> (45, 25.5)
  line L7 (45, 25.5) -> (45, 15)
  circle A70 centre (-48, 17) radius 1.5
  circle A71 centre (-48, 23) radius 1.5
  circle A72 centre (-48, 11) radius 1.5
  circle A73 centre (-48, 5) radius 1.5
  circle A74 centre (-48, 29) radius 1.5
  circle A75 centre (47, 23) radius 1.5
  circle A76 centre (47, 17) radius 1.5
  circle A77 centre (47, 5) radius 1.5
  circle A78 centre (47, 29) radius 1.5
  circle A79 centre (47, 11) radius 1.5
  constraint horizontal L4
  constraint vertical L5
  constraint horizontal L6
  constraint vertical L7
extrude "Extrude8" cut sketch "Sketch9" against normal blind 15 contours L4 L5 L6 L7 bodies 1
ref_plane "WorkPlane1" through (0, 17, -4) normal (0, 0, 1) x (1, 0, 0)
sketch "Sketch10" plane through (0, 0, -4) normal (0, 0, 1) x (1, 0, 0)
  arc A0 (-37.9, 13) -> (-22.1, 13) centre (-30, 13) ccw
  arc A1 (-38.9, 13) -> (-21.1, 13) centre (-30, 13) ccw
  line L0 (-21.1, 13) -> (-22.1, 13)
  line L1 (-37.9, 13) -> (-38.9, 13)
  line L2 (-29.5, 4.1663) -> (-29.5, 4.1141)
  dimension "d58" = 15.8
  constraint concentric A0 A1
  constraint collinear L0 L1
  constraint vertical L2
  constraint coincident A1 L2.end
  measures "d58" diameter of A0
extrude "Extrude9" add sketch "Sketch10" along normal blind 2 separate body makes body 2
move_body "Move2" bodies 2 to x (1, 0, 0) y (0, 1, 0) z (0, 0, 1) at (0, -3, 0)
copy_body "CopyPasteBodies1" bodies 2 makes body 3
move_body "Move3" bodies 3 to x (1, 0, 0) y (0, 1, 0) z (0, 0, 1) at (0, 0, -26)
move_face "OffsetFaces2" offset 0.5 6 faces at (-26.7508, 2.7991, -3.3333) (-21.4333, 10, -3.3333) (-38.2333, 10, -3.3333) (-26.7508, 2.7991, -28.6667) (-38.2333, 10, -29.3333) (-21.4333, 10, -29.3333) on bodies 2 3
combine "Combine1" operation add target body 1 tool bodies 3 2
move_face "OffsetFaces3" offset 10 4 faces at (52.5, 16.3333, 51.1667) (-51.041, 16.2826, 52.5) (-52.5, 16.3333, 51.1667) (-51.041, 16.2826, -52.5) on bodies 1
extrude "Extrude10" cut 1 faces at (-52, 17, 50.8333) along direction (-1, 0, 0) blind 5 on bodies 1 bodies 1
extrude "Extrude11" cut 1 faces at (-54.041, 16.9493, 52) along direction (0, 0, 1) blind 5 on bodies 1 bodies 1
extrude "Extrude12" cut 1 faces at (52, 17, 54.1667) along direction (1, 0, 0) blind 5 on bodies 1 bodies 1
extrude "Extrude13" cut 1 faces at (-54.041, 16.9493, -52) along direction (0, 0, -1) blind 5 on bodies 1 bodies 1
sketch "Sketch11" plane through (0, 32, 0) normal (0, 1, 0) x (-1, 0, 0)
  line L0 (-62.5, -62.5) -> (62.5, -62.5)
  line L1 (62.5, -62.5) -> (62.5, 62.5)
  line L2 (62.5, 62.5) -> (-62.5, 62.5)
  line L3 (-62.5, 62.5) -> (-62.5, -62.5)
  circle A0 centre (59.75, -59.75) radius 1.5
  circle A1 centre (-59.75, -59.75) radius 1.5
  circle A2 centre (59.75, 59.75) radius 1.5
  circle A3 centre (-59.75, 59.75) radius 1.5
  circle A4 centre (54, -54) radius 1.5
  circle A5 centre (46.2857, -54) radius 1.5
  circle A6 centre (38.5714, -54) radius 1.5
  circle A7 centre (30.8571, -54) radius 1.5
  circle A8 centre (23.1429, -54) radius 1.5
  circle A9 centre (15.4286, -54) radius 1.5
  circle A10 centre (7.7143, -54) radius 1.5
  circle A11 centre (0, -54) radius 1.5
  circle A12 centre (-7.7143, -54) radius 1.5
  circle A13 centre (-15.4286, -54) radius 1.5
  circle A14 centre (-23.1429, -54) radius 1.5
  circle A15 centre (-30.8571, -54) radius 1.5
  circle A16 centre (-38.5714, -54) radius 1.5
  circle A17 centre (-46.2857, -54) radius 1.5
  circle A18 centre (-54, -54) radius 1.5
  circle A19 centre (54, -46.2857) radius 1.5
  circle A20 centre (46.2857, -46.2857) radius 1.5
  circle A21 centre (38.5714, -46.2857) radius 1.5
  circle A22 centre (30.8571, -46.2857) radius 1.5
  circle A23 centre (23.1429, -46.2857) radius 1.5
  circle A24 centre (15.4286, -46.2857) radius 1.5
  circle A25 centre (7.7143, -46.2857) radius 1.5
  circle A26 centre (0, -46.2857) radius 1.5
  circle A27 centre (-7.7143, -46.2857) radius 1.5
  circle A28 centre (-15.4286, -46.2857) radius 1.5
  circle A29 centre (-23.1429, -46.2857) radius 1.5
  circle A30 centre (-30.8571, -46.2857) radius 1.5
  circle A31 centre (-38.5714, -46.2857) radius 1.5
  circle A32 centre (-46.2857, -46.2857) radius 1.5
  circle A33 centre (-54, -46.2857) radius 1.5
  circle A34 centre (54, -38.5714) radius 1.5
  circle A35 centre (46.2857, -38.5714) radius 1.5
  circle A36 centre (38.5714, -38.5714) radius 1.5
  circle A37 centre (30.8571, -38.5714) radius 1.5
  circle A38 centre (23.1429, -38.5714) radius 1.5
  circle A39 centre (15.4286, -38.5714) radius 1.5
  circle A40 centre (7.7143, -38.5714) radius 1.5
  circle A41 centre (0, -38.5714) radius 1.5
  circle A42 centre (-7.7143, -38.5714) radius 1.5
  circle A43 centre (-15.4286, -38.5714) radius 1.5
  circle A44 centre (-23.1429, -38.5714) radius 1.5
  circle A45 centre (-30.8571, -38.5714) radius 1.5
  circle A46 centre (-38.5714, -38.5714) radius 1.5
  circle A47 centre (-46.2857, -38.5714) radius 1.5
  circle A48 centre (-54, -38.5714) radius 1.5
  circle A49 centre (54, -30.8571) radius 1.5
  circle A50 centre (46.2857, -30.8571) radius 1.5
  circle A51 centre (38.5714, -30.8571) radius 1.5
  circle A52 centre (30.8571, -30.8571) radius 1.5
  circle A53 centre (23.1429, -30.8571) radius 1.5
  circle A54 centre (15.4286, -30.8571) radius 1.5
  circle A55 centre (7.7143, -30.8571) radius 1.5
  circle A56 centre (0, -30.8571) radius 1.5
  circle A57 centre (-7.7143, -30.8571) radius 1.5
  circle A58 centre (-15.4286, -30.8571) radius 1.5
  circle A59 centre (-23.1429, -30.8571) radius 1.5
  circle A60 centre (-30.8571, -30.8571) radius 1.5
  circle A61 centre (-38.5714, -30.8571) radius 1.5
  circle A62 centre (-46.2857, -30.8571) radius 1.5
  circle A63 centre (-54, -30.8571) radius 1.5
  circle A64 centre (54, -23.1429) radius 1.5
  circle A65 centre (46.2857, -23.1429) radius 1.5
  circle A66 centre (38.5714, -23.1429) radius 1.5
  circle A67 centre (30.8571, -23.1429) radius 1.5
  circle A68 centre (23.1429, -23.1429) radius 1.5
  circle A69 centre (15.4286, -23.1429) radius 1.5
  circle A70 centre (7.7143, -23.1429) radius 1.5
  circle A71 centre (0, -23.1429) radius 1.5
  circle A72 centre (-7.7143, -23.1429) radius 1.5
  circle A73 centre (-15.4286, -23.1429) radius 1.5
  circle A74 centre (-23.1429, -23.1429) radius 1.5
  circle A75 centre (-30.8571, -23.1429) radius 1.5
  circle A76 centre (-38.5714, -23.1429) radius 1.5
  circle A77 centre (-46.2857, -23.1429) radius 1.5
  circle A78 centre (-54, -23.1429) radius 1.5
  circle A79 centre (54, -15.4286) radius 1.5
  circle A80 centre (46.2857, -15.4286) radius 1.5
  circle A81 centre (38.5714, -15.4286) radius 1.5
  circle A82 centre (30.8571, -15.4286) radius 1.5
  circle A83 centre (23.1429, -15.4286) radius 1.5
  circle A84 centre (15.4286, -15.4286) radius 1.5
  circle A85 centre (7.7143, -15.4286) radius 1.5
  circle A86 centre (0, -15.4286) radius 1.5
  circle A87 centre (-7.7143, -15.4286) radius 1.5
  circle A88 centre (-15.4286, -15.4286) radius 1.5
  circle A89 centre (-23.1429, -15.4286) radius 1.5
  circle A90 centre (-30.8571, -15.4286) radius 1.5
  circle A91 centre (-38.5714, -15.4286) radius 1.5
  circle A92 centre (-46.2857, -15.4286) radius 1.5
  circle A93 centre (-54, -15.4286) radius 1.5
  circle A94 centre (54, -7.7143) radius 1.5
  circle A95 centre (46.2857, -7.7143) radius 1.5
  circle A96 centre (38.5714, -7.7143) radius 1.5
  circle A97 centre (30.8571, -7.7143) radius 1.5
  circle A98 centre (23.1429, -7.7143) radius 1.5
  circle A99 centre (15.4286, -7.7143) radius 1.5
  circle A100 centre (7.7143, -7.7143) radius 1.5
  circle A101 centre (0, -7.7143) radius 1.5
  circle A102 centre (-7.7143, -7.7143) radius 1.5
  circle A103 centre (-15.4286, -7.7143) radius 1.5
  circle A104 centre (-23.1429, -7.7143) radius 1.5
  circle A105 centre (-30.8571, -7.7143) radius 1.5
  circle A106 centre (-38.5714, -7.7143) radius 1.5
  circle A107 centre (-46.2857, -7.7143) radius 1.5
  circle A108 centre (-54, -7.7143) radius 1.5
  circle A109 centre (54, 0) radius 1.5
  circle A110 centre (46.2857, 0) radius 1.5
  circle A111 centre (38.5714, 0) radius 1.5
  circle A112 centre (30.8571, 0) radius 1.5
  circle A113 centre (23.1429, 0) radius 1.5
  circle A114 centre (15.4286, 0) radius 1.5
  circle A115 centre (7.7143, 0) radius 1.5
  circle A116 centre (0, 0) radius 1.5
  circle A117 centre (-7.7143, 0) radius 1.5
  circle A118 centre (-15.4286, 0) radius 1.5
  circle A119 centre (-23.1429, 0) radius 1.5
  circle A120 centre (-30.8571, 0) radius 1.5
  circle A121 centre (-38.5714, 0) radius 1.5
  circle A122 centre (-46.2857, 0) radius 1.5
  circle A123 centre (-54, 0) radius 1.5
  circle A124 centre (54, 7.7143) radius 1.5
  circle A125 centre (46.2857, 7.7143) radius 1.5
  circle A126 centre (38.5714, 7.7143) radius 1.5
  circle A127 centre (30.8571, 7.7143) radius 1.5
  circle A128 centre (23.1429, 7.7143) radius 1.5
  circle A129 centre (15.4286, 7.7143) radius 1.5
  circle A130 centre (7.7143, 7.7143) radius 1.5
  circle A131 centre (0, 7.7143) radius 1.5
  circle A132 centre (-7.7143, 7.7143) radius 1.5
  circle A133 centre (-15.4286, 7.7143) radius 1.5
  circle A134 centre (-23.1429, 7.7143) radius 1.5
  circle A135 centre (-30.8571, 7.7143) radius 1.5
  circle A136 centre (-38.5714, 7.7143) radius 1.5
  circle A137 centre (-46.2857, 7.7143) radius 1.5
  circle A138 centre (-54, 7.7143) radius 1.5
  circle A139 centre (54, 15.4286) radius 1.5
  circle A140 centre (46.2857, 15.4286) radius 1.5
  circle A141 centre (38.5714, 15.4286) radius 1.5
  circle A142 centre (30.8571, 15.4286) radius 1.5
  circle A143 centre (23.1429, 15.4286) radius 1.5
  circle A144 centre (15.4286, 15.4286) radius 1.5
  circle A145 centre (7.7143, 15.4286) radius 1.5
  circle A146 centre (0, 15.4286) radius 1.5
  circle A147 centre (-7.7143, 15.4286) radius 1.5
  circle A148 centre (-15.4286, 15.4286) radius 1.5
  circle A149 centre (-23.1429, 15.4286) radius 1.5
  circle A150 centre (-30.8571, 15.4286) radius 1.5
  circle A151 centre (-38.5714, 15.4286) radius 1.5
  circle A152 centre (-46.2857, 15.4286) radius 1.5
  circle A153 centre (-54, 15.4286) radius 1.5
  circle A154 centre (54, 23.1429) radius 1.5
  circle A155 centre (46.2857, 23.1429) radius 1.5
  circle A156 centre (38.5714, 23.1429) radius 1.5
  circle A157 centre (30.8571, 23.1429) radius 1.5
  circle A158 centre (23.1429, 23.1429) radius 1.5
  circle A159 centre (15.4286, 23.1429) radius 1.5
  circle A160 centre (7.7143, 23.1429) radius 1.5
  circle A161 centre (0, 23.1429) radius 1.5
  circle A162 centre (-7.7143, 23.1429) radius 1.5
  circle A163 centre (-15.4286, 23.1429) radius 1.5
  circle A164 centre (-23.1429, 23.1429) radius 1.5
  circle A165 centre (-30.8571, 23.1429) radius 1.5
  circle A166 centre (-38.5714, 23.1429) radius 1.5
  circle A167 centre (-46.2857, 23.1429) radius 1.5
  circle A168 centre (-54, 23.1429) radius 1.5
  circle A169 centre (54, 30.8571) radius 1.5
  circle A170 centre (46.2857, 30.8571) radius 1.5
  circle A171 centre (38.5714, 30.8571) radius 1.5
  circle A172 centre (30.8571, 30.8571) radius 1.5
  circle A173 centre (23.1429, 30.8571) radius 1.5
  circle A174 centre (15.4286, 30.8571) radius 1.5
  circle A175 centre (7.7143, 30.8571) radius 1.5
  circle A176 centre (0, 30.8571) radius 1.5
  circle A177 centre (-7.7143, 30.8571) radius 1.5
  circle A178 centre (-15.4286, 30.8571) radius 1.5
  circle A179 centre (-23.1429, 30.8571) radius 1.5
  circle A180 centre (-30.8571, 30.8571) radius 1.5
  circle A181 centre (-38.5714, 30.8571) radius 1.5
  circle A182 centre (-46.2857, 30.8571) radius 1.5
  circle A183 centre (-54, 30.8571) radius 1.5
  circle A184 centre (54, 38.5714) radius 1.5
  circle A185 centre (46.2857, 38.5714) radius 1.5
  circle A186 centre (38.5714, 38.5714) radius 1.5
  circle A187 centre (30.8571, 38.5714) radius 1.5
  circle A188 centre (23.1429, 38.5714) radius 1.5
  circle A189 centre (15.4286, 38.5714) radius 1.5
  circle A190 centre (7.7143, 38.5714) radius 1.5
  circle A191 centre (0, 38.5714) radius 1.5
  circle A192 centre (-7.7143, 38.5714) radius 1.5
  circle A193 centre (-15.4286, 38.5714) radius 1.5
  circle A194 centre (-23.1429, 38.5714) radius 1.5
  circle A195 centre (-30.8571, 38.5714) radius 1.5
  circle A196 centre (-38.5714, 38.5714) radius 1.5
  circle A197 centre (-46.2857, 38.5714) radius 1.5
  circle A198 centre (-54, 38.5714) radius 1.5
  circle A199 centre (54, 46.2857) radius 1.5
  circle A200 centre (46.2857, 46.2857) radius 1.5
  circle A201 centre (38.5714, 46.2857) radius 1.5
  circle A202 centre (30.8571, 46.2857) radius 1.5
  circle A203 centre (23.1429, 46.2857) radius 1.5
  circle A204 centre (15.4286, 46.2857) radius 1.5
  circle A205 centre (7.7143, 46.2857) radius 1.5
  circle A206 centre (0, 46.2857) radius 1.5
  circle A207 centre (-7.7143, 46.2857) radius 1.5
  circle A208 centre (-15.4286, 46.2857) radius 1.5
  circle A209 centre (-23.1429, 46.2857) radius 1.5
  circle A210 centre (-30.8571, 46.2857) radius 1.5
  circle A211 centre (-38.5714, 46.2857) radius 1.5
  circle A212 centre (-46.2857, 46.2857) radius 1.5
  circle A213 centre (-54, 46.2857) radius 1.5
  circle A214 centre (54, 54) radius 1.5
  circle A215 centre (46.2857, 54) radius 1.5
  circle A216 centre (38.5714, 54) radius 1.5
  circle A217 centre (30.8571, 54) radius 1.5
  circle A218 centre (23.1429, 54) radius 1.5
  circle A219 centre (15.4286, 54) radius 1.5
  circle A220 centre (7.7143, 54) radius 1.5
  circle A221 centre (0, 54) radius 1.5
  circle A222 centre (-7.7143, 54) radius 1.5
  circle A223 centre (-15.4286, 54) radius 1.5
  circle A224 centre (-23.1429, 54) radius 1.5
  circle A225 centre (-30.8571, 54) radius 1.5
  circle A226 centre (-38.5714, 54) radius 1.5
  circle A227 centre (-46.2857, 54) radius 1.5
  circle A228 centre (-54, 54) radius 1.5
  dimension "d72" = 3
  dimension "d77" = 3
  dimension "d80" = 108
  dimension "d81" = 108
  measures "d72" diameter of A0
  measures "d77" diameter of A4
extrude "Extrude14" add sketch "Sketch11" along normal blind 2 separate body makes body 4
move_body "Move4" bodies 4 to x (1, 0, 0) y (0, 1, 0) z (0, 0, 1) at (140, -32, 0)
